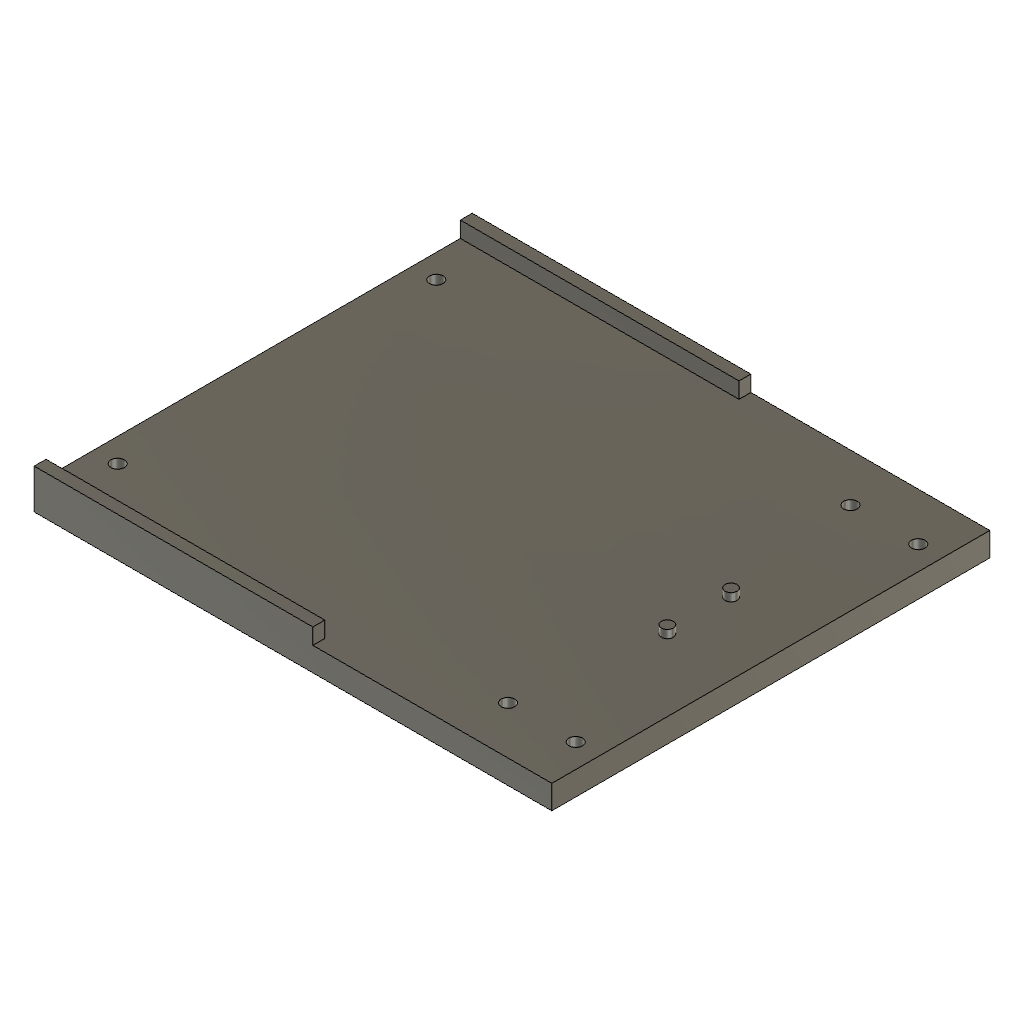
weighted_root_base (Autodesk Fusion 360 design; units mm, degrees)
part number: 2026-10-11-03-14-10-781
Autodesk Fusion 360 part; units mm, degrees
sketch "Flat root support floor sketch" plane through (0, 0, 0) normal (0, 0, 1) x (1, 0, 0)
  line L0 (-104, -55) -> (26, -55)
  line L1 (26, -55) -> (26, 55)
  line L2 (26, 55) -> (-104, 55)
  line L3 (-104, 55) -> (-104, -55)
extrude "Flat root support floor" add sketch "Flat root support floor sketch" along normal blind 6
ref_plane "WorkPlane1" through (0, 0, 5.95) normal (0, 0, 1) x (1, 0, 0)
sketch "Front tray side lip -55 sketch" plane through (0, 0, 5.95) normal (0, 0, 1) x (1, 0, 0)
  line L0 (-104, -55) -> (-34, -55)
  line L1 (-34, -55) -> (-34, -52)
  line L2 (-34, -52) -> (-104, -52)
  line L3 (-104, -52) -> (-104, -55)
extrude "Front tray side lip -55" add sketch "Front tray side lip -55 sketch" along normal blind 4.05
ref_plane "WorkPlane2" through (0, 0, 5.95) normal (0, 0, 1) x (1, 0, 0)
sketch "Front tray side lip 52 sketch" plane through (0, 0, 5.95) normal (0, 0, 1) x (1, 0, 0)
  line L0 (-104, 52) -> (-34, 52)
  line L1 (-34, 52) -> (-34, 55)
  line L2 (-34, 55) -> (-104, 55)
  line L3 (-104, 55) -> (-104, 52)
extrude "Front tray side lip 52" add sketch "Front tray side lip 52 sketch" along normal blind 4.05
ref_plane "WorkPlane3" through (0, 0, 5.95) normal (0, 0, 1) x (1, 0, 0)
sketch "Original root locating pin -8" plane through (0, 0, 5.95) normal (0, 0, 1) x (1, 0, 0)
  circle A0 centre (8, -8) radius 1.5
extrude "Root locating pin -8" add sketch "Original root locating pin -8" along normal blind 2.05
ref_plane "WorkPlane4" through (0, 0, 5.95) normal (0, 0, 1) x (1, 0, 0)
sketch "Original root locating pin 8" plane through (0, 0, 5.95) normal (0, 0, 1) x (1, 0, 0)
  circle A0 centre (8, 8) radius 1.5
extrude "Root locating pin 8" add sketch "Original root locating pin 8" along normal blind 2.05
ref_plane "WorkPlane5" through (0, 0, -0.05) normal (0, 0, 1) x (1, 0, 0)
sketch "Root bolt (3, -43) clearance sketch" plane through (0, 0, -0.05) normal (0, 0, 1) x (1, 0, 0)
  circle A0 centre (3, -43) radius 1.7
  dimension "d25" = 3.4
  measures "d25" diameter of A0
extrude "Root bolt (3, -43) clearance" cut sketch "Root bolt (3, -43) clearance sketch" along normal blind 6.1
ref_plane "WorkPlane6" through (0, 0, -0.05) normal (0, 0, 1) x (1, 0, 0)
sketch "Root bolt (3, -43) recessed head sketch" plane through (0, 0, -0.05) normal (0, 0, 1) x (1, 0, 0)
  circle A0 centre (3, -43) radius 3.2
  dimension "d30" = 6.4
  measures "d30" diameter of A0
extrude "Root bolt (3, -43) recessed head" cut sketch "Root bolt (3, -43) recessed head sketch" along normal blind 3.4
ref_plane "WorkPlane7" through (0, 0, -0.05) normal (0, 0, 1) x (1, 0, 0)
sketch "Root bolt (3, 43) clearance sketch" plane through (0, 0, -0.05) normal (0, 0, 1) x (1, 0, 0)
  circle A0 centre (3, 43) radius 1.7
  dimension "d35" = 3.4
  measures "d35" diameter of A0
extrude "Root bolt (3, 43) clearance" cut sketch "Root bolt (3, 43) clearance sketch" along normal blind 6.1
ref_plane "WorkPlane8" through (0, 0, -0.05) normal (0, 0, 1) x (1, 0, 0)
sketch "Root bolt (3, 43) recessed head sketch" plane through (0, 0, -0.05) normal (0, 0, 1) x (1, 0, 0)
  circle A0 centre (3, 43) radius 3.2
  dimension "d40" = 6.4
  measures "d40" diameter of A0
extrude "Root bolt (3, 43) recessed head" cut sketch "Root bolt (3, 43) recessed head sketch" along normal blind 3.4
ref_plane "WorkPlane9" through (0, 0, -0.05) normal (0, 0, 1) x (1, 0, 0)
sketch "Root bolt (20, -43) clearance sketch" plane through (0, 0, -0.05) normal (0, 0, 1) x (1, 0, 0)
  circle A0 centre (20, -43) radius 1.7
  dimension "d45" = 3.4
  measures "d45" diameter of A0
extrude "Root bolt (20, -43) clearance" cut sketch "Root bolt (20, -43) clearance sketch" along normal blind 6.1
ref_plane "WorkPlane10" through (0, 0, -0.05) normal (0, 0, 1) x (1, 0, 0)
sketch "Root bolt (20, -43) recessed head sketch" plane through (0, 0, -0.05) normal (0, 0, 1) x (1, 0, 0)
  circle A0 centre (20, -43) radius 3.2
  dimension "d50" = 6.4
  measures "d50" diameter of A0
extrude "Root bolt (20, -43) recessed head" cut sketch "Root bolt (20, -43) recessed head sketch" along normal blind 3.4
ref_plane "WorkPlane11" through (0, 0, -0.05) normal (0, 0, 1) x (1, 0, 0)
sketch "Root bolt (20, 43) clearance sketch" plane through (0, 0, -0.05) normal (0, 0, 1) x (1, 0, 0)
  circle A0 centre (20, 43) radius 1.7
  dimension "d55" = 3.4
  measures "d55" diameter of A0
extrude "Root bolt (20, 43) clearance" cut sketch "Root bolt (20, 43) clearance sketch" along normal blind 6.1
ref_plane "WorkPlane12" through (0, 0, -0.05) normal (0, 0, 1) x (1, 0, 0)
sketch "Root bolt (20, 43) recessed head sketch" plane through (0, 0, -0.05) normal (0, 0, 1) x (1, 0, 0)
  circle A0 centre (20, 43) radius 3.2
  dimension "d60" = 6.4
  measures "d60" diameter of A0
extrude "Root bolt (20, 43) recessed head" cut sketch "Root bolt (20, 43) recessed head sketch" along normal blind 3.4
ref_plane "WorkPlane13" through (0, 0, -0.05) normal (0, 0, 1) x (1, 0, 0)
sketch "Tray joint front bolt -40 clearance sketch" plane through (0, 0, -0.05) normal (0, 0, 1) x (1, 0, 0)
  circle A0 centre (-98, -40) radius 1.7
  dimension "d65" = 3.4
  measures "d65" diameter of A0
extrude "Tray joint front bolt -40 clearance" cut sketch "Tray joint front bolt -40 clearance sketch" along normal blind 6.1
ref_plane "WorkPlane14" through (0, 0, -0.05) normal (0, 0, 1) x (1, 0, 0)
sketch "Tray joint front bolt -40 recessed head sketch" plane through (0, 0, -0.05) normal (0, 0, 1) x (1, 0, 0)
  circle A0 centre (-98, -40) radius 3.2
  dimension "d70" = 6.4
  measures "d70" diameter of A0
extrude "Tray joint front bolt -40 recessed head" cut sketch "Tray joint front bolt -40 recessed head sketch" along normal blind 3.4
ref_plane "WorkPlane15" through (0, 0, -0.05) normal (0, 0, 1) x (1, 0, 0)
sketch "Tray joint front bolt 40 clearance sketch" plane through (0, 0, -0.05) normal (0, 0, 1) x (1, 0, 0)
  circle A0 centre (-98, 40) radius 1.7
  dimension "d75" = 3.4
  measures "d75" diameter of A0
extrude "Tray joint front bolt 40 clearance" cut sketch "Tray joint front bolt 40 clearance sketch" along normal blind 6.1
ref_plane "WorkPlane16" through (0, 0, -0.05) normal (0, 0, 1) x (1, 0, 0)
sketch "Tray joint front bolt 40 recessed head sketch" plane through (0, 0, -0.05) normal (0, 0, 1) x (1, 0, 0)
  circle A0 centre (-98, 40) radius 3.2
  dimension "d80" = 6.4
  measures "d80" diameter of A0
extrude "Tray joint front bolt 40 recessed head" cut sketch "Tray joint front bolt 40 recessed head sketch" along normal blind 3.4
equation "d5 = standFloor"
equation "d25 = m3Clearance"
equation "d30 = m3HeadClearance"
equation "d35 = m3Clearance"
equation "d40 = m3HeadClearance"
equation "d45 = m3Clearance"
equation "d50 = m3HeadClearance"
equation "d55 = m3Clearance"
equation "d60 = m3HeadClearance"
equation "d65 = m3Clearance"
equation "d70 = m3HeadClearance"
equation "d75 = m3Clearance"
equation "d80 = m3HeadClearance"
equation "m3Clearance = 3.4 mm" comment "Weighted stand"
equation "m3HeadClearance = 6.4 mm" comment "Weighted stand"
equation "standFloor = 6 mm" comment "Weighted stand"
named bodies: "weighted_root_base native printable solid"
